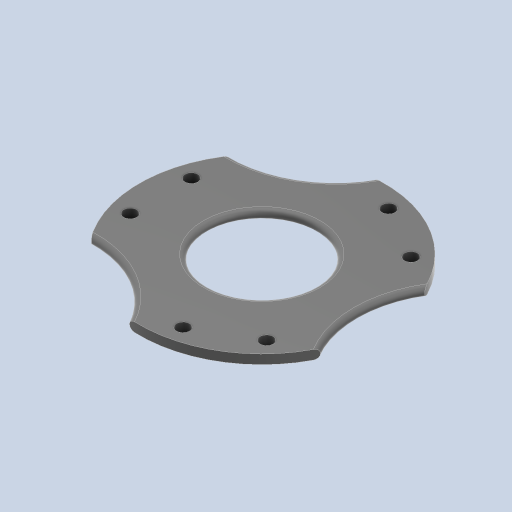
# Autodesk Inventor part: Suporte perfil
Saved by Autodesk Inventor 2026.1 (Build 301233020, 233B)
## iProperties
Created: 2025-01-12
Part Number: Suporte perfil
Material: ABS plástico
Document SubType Name: Modeling
Designer: Cliente
Density: 0.970536 g/cm^3
Appearance: Suave - Branco
Mass: 9.7 g
Surface Area: 78.5519 cm^2
Volume: 9.99448 cm^3
Author: Cliente
Autodesk Inventor part; units mm, degrees
ref_plane "YZ Plane" through (0, 0, 0) normal (1, 0, 0) x (0, 1, 0)
ref_plane "XZ Plane" through (0, 0, 0) normal (0, 1, 0) x (-1, 0, 0)
ref_plane "XY Plane" through (0, 0, 0) normal (0, 0, 1) x (1, 0, 0)
sketch "Esboço1" plane through (0, 0, 0) normal (0, 1, 0) x (-1, 0, 0)
  circle A0 centre (0, 0) radius 40
  line L0 (0, 0) -> (33, 0)
  line L1 (33, -10) -> (33, 10)
  circle A1 centre (33, -10) radius 2.15
  circle A2 centre (33, 10) radius 2.15
  circle A3 centre (-25.1603, 23.5788) radius 2.15
  circle A4 centre (-7.8397, 33.5788) radius 2.15
  circle A5 centre (-7.8397, -33.5788) radius 2.15
  circle A6 centre (-25.1603, -23.5788) radius 2.15
  dimension "d0" = 80
  dimension "d1" = 33
  dimension "d2" = 20
  dimension "d3" = 4.3
  dimension "d4" = 4.3
  dimension "d7" = 360
  constraints: 7 centre point, 4 end point, 3 coincident, 1 horizontal, 1 midpoint, 1 vertical, 13 other
  measures "d0" diameter of A0
  measures "d1" distance of L0.end L0.start
  measures "d2" distance of L1.start L1.end
  measures "d3" diameter of A1
  measures "d4" diameter of A2
extrude "Extrusão1" add sketch "Esboço1" along normal blind 3
sketch "Esboço2" plane through (0, 3, 0) normal (0, 1, 0) x (1, 0, 0)
  line L0 (0, 0) -> (36.2077, 0)
  line L1 (36.2077, 17) -> (36.2077, -17)
  circle A0 centre (0, 0) radius 40 projected
  arc A1 (36.2077, 17) -> (36.2077, -17) centre (65.6526, 0) ccw
  line L2 (36.2077, -17) -> (26.3928, 0)
  line L3 (36.2077, -17) -> (55.8376, -17) construction
  arc A2 (-32.8263, 22.8568) -> (-3.3814, 39.8568) centre (-32.8263, 56.8568) ccw
  arc A3 (-3.3814, -39.8568) -> (-32.8263, -22.8568) centre (-32.8263, -56.8568) ccw
  point P0 (36.2077, -17)
  point P1 (-32.8263, 22.8568)
  point P2 (-3.3814, 39.8568)
  point P3 (-3.3814, -39.8568)
  point P4 (-32.8263, -22.8568)
  dimension "d11" = 34
  dimension "d12" = 120
  dimension "d15" = 360
  constraints: 8 end point, 6 point on circle, 3 centre point, 2 horizontal, 1 equal length, 1 midpoint, 1 point on line, 1 tangent, 1 vertical, 15 other
  measures "d11" distance of L1.start L1.end
  measures "d12" angle of L3 L2
extrude "Extrusão2" cut sketch "Esboço2" against normal blind 3 contours A1 L1 L0 | L0 L1 A1 | L1 A0 | A0 A3 | A2 A0
sketch "Esboço3" plane through (0, 3, 0) normal (0, 1, 0) x (1, 0, 0)
  circle A0 centre (0, 0) radius 17.5
  dimension "d19" = 35
  constraints: 1 centre point, 1 coincident
  measures "d19" diameter of A0
extrude "Extrusão3" cut sketch "Esboço3" against normal blind 3
fillet "Arredondamento1" radius 1.5 8 edges at (-17.5, 3, 0) (-17.5, 0, 0) (31.6526, 3, 0) (31.6526, 0, 0) (-15.8263, 3, 27.412) (-15.8263, 0, 27.412) (-15.8263, 3, -27.412) (-15.8263, 0, -27.412)
